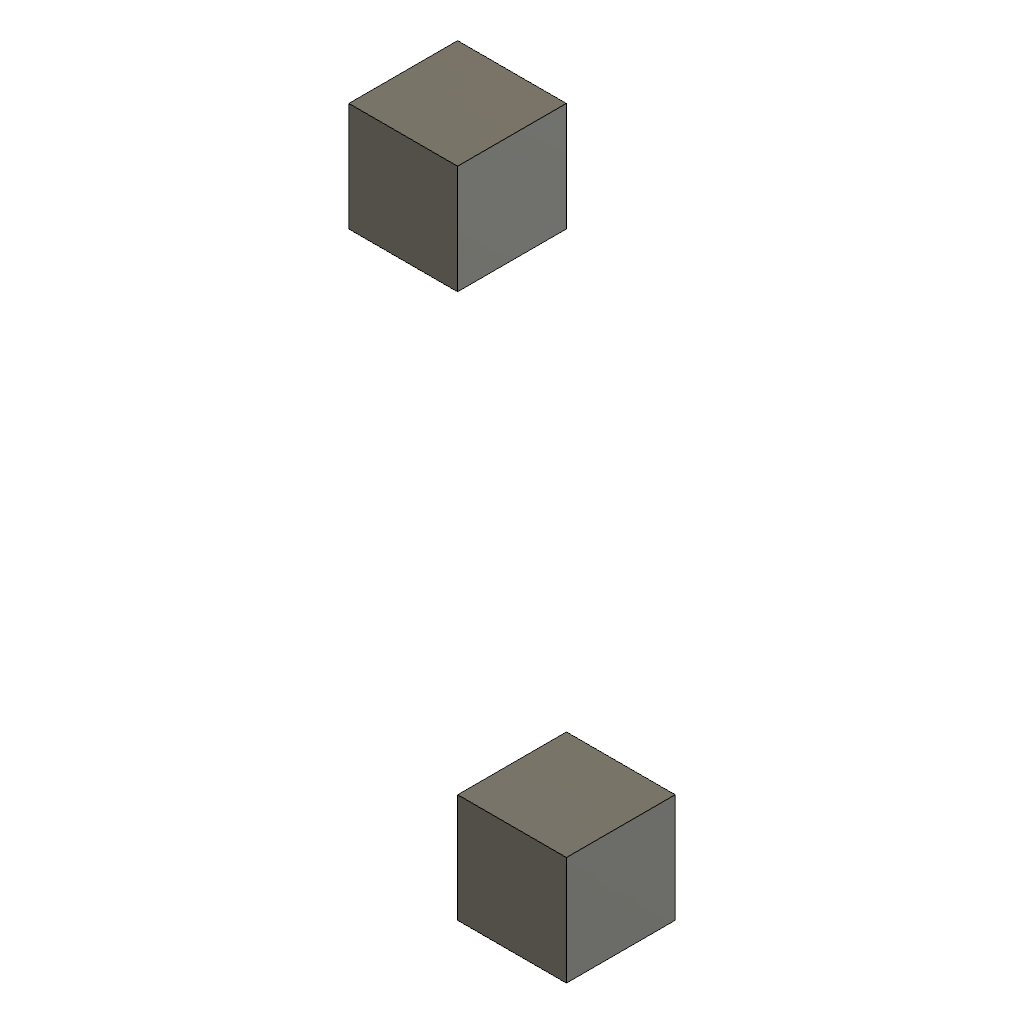
revolute (Autodesk Fusion 360 design; units mm, degrees)
part number: 2026-10-21-11-34-46-705
part number: 2026-10-21-11-34-46-881
part number: 2026-10-21-11-34-46-891
Autodesk Fusion 360 part; units mm, degrees
sketch "AsBuiltFixedProfile" plane through (0, 0, 0) normal (0, 0, 1) x (1, 0, 0) in component "AsBuiltFixed"
  line L0 (0, 0) -> (10, 0)
  line L1 (10, 0) -> (10, 10)
  line L2 (10, 10) -> (0, 10)
  line L3 (0, 10) -> (0, 0)
extrude "AsBuiltFixedExtrude" add sketch "AsBuiltFixedProfile" along normal blind 10 makes body 1 in component "AsBuiltFixed"
sketch "AsBuiltMovingProfile" plane through (0, 0, 0) normal (0, 0, 1) x (1, 0, 0) in component "AsBuiltMoving"
  line L0 (0, 0) -> (10, 0)
  line L1 (10, 0) -> (10, 10)
  line L2 (10, 10) -> (0, 10)
  line L3 (0, 10) -> (0, 0)
extrude "AsBuiltMovingExtrude" add sketch "AsBuiltMovingProfile" along normal blind 10 separate body makes body 2 in component "AsBuiltMoving"
component "AsBuiltFixed" placed x (1, 0, 0) y (0, 1, 0) z (0, 0, 1) at (10, 20, 0)
component "AsBuiltMoving" placed x (1, 0, 0) y (0, 1, 0) z (0, 0, 1) at (40, -10, 20)
named bodies: "AsBuiltFixedBody", "AsBuiltMovingBody"
